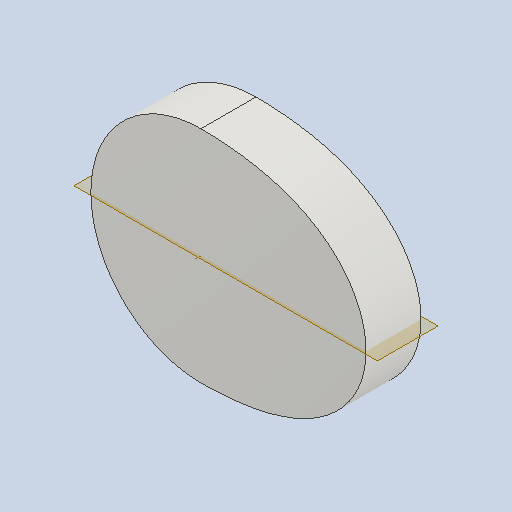
# Autodesk Inventor part: Disc Cam
Saved by Autodesk Inventor 2025.2 (Build 292293000, 293)
## iProperties
CustomPartVersion: 1
Created: 2025-05-16
Part Number: Disc Cam
Material: Stainless Steel, Austenitic
Document SubType Name: Modeling
Designer: laura
Manufacturer: Standard
Standards Organization: Custom
Density: 1 g/cm^3
Appearance: Steel
Author: laura
Autodesk Inventor part; units mm, degrees
ref_plane "YZ Plane" through (0, 0, 0) normal (1, 0, 0) x (0, 1, 0)
ref_plane "XY Plane" through (0, 0, 0) normal (0, 0, 1) x (1, 0, 0)
sketch "Main Sketch" plane through (0, 0, 0) normal (0, 0, 1) x (1, 0, 0)
  spline S0 degree 5 poles (0, 12) (0.4028, 12.0029) (1.1352, 11.9904) (2.4035, 11.9385) (3.7305, 11.8234) (5.6073, 11.5664) (7.2429, 11.2248) (8.9199, 10.7506) (10.4855, 10.155) (11.9526, 9.4335) (13.2947, 8.5866) (14.5002, 7.6184) (15.5512, 6.5376) (16.4335, 5.357) (17.1335, 4.0932) (17.641, 2.7651) (17.9484, 1.3935) (18.0513, 0) (17.9484, -1.3935) (17.641, -2.7651) (17.1335, -4.0932) (16.4335, -5.357) (15.5512, -6.5376) (14.5002, -7.6184) (13.2947, -8.5866) (11.9526, -9.4335) (10.4857, -10.1549) (8.9195, -10.7506) (7.2438, -11.2248) (5.5475, -11.5786) (3.7134, -11.8248) (2.115, -11.9626) (0.0437, -12.0261) (-1.0836, -11.9872) (-2.4837, -11.7795) (-3.6974, -11.4488) (-4.8987, -10.9923) (-6.0146, -10.421) (-7.0736, -9.7348) (-8.0513, -8.9422) (-8.9424, -8.0516) (-9.7348, -7.0728) (-10.4209, -6.0165) (-10.9926, -4.8942) (-11.444, -3.7184) (-11.77, -2.5018) (-11.967, -1.2578) (-12.0329, 0) (-11.967, 1.2578) (-11.77, 2.5018) (-11.444, 3.7184) (-10.9926, 4.8942) (-10.4209, 6.0165) (-9.7348, 7.0728) (-8.9424, 8.0516) (-8.0511, 8.9423) (-7.074, 9.7348) (-6.0137, 10.421) (-4.9008, 10.9922) (-3.7511, 11.4269) (-2.5835, 11.7561) (-1.505, 11.9244) (-0.839, 11.9821) (-0.3306, 11.9976) (0, 12) knots 0 0 0 0 0 0 0.0229 0.038048 0.056871 0.075478 0.093836 0.111931 0.129762 0.147341 0.164681 0.181803 0.198727 0.215484 0.232106 0.248635 0.265115 0.281595 0.298123 0.314745 0.331502 0.348427 0.365548 0.382888 0.400467 0.418299 0.436394 0.454752 0.473359 0.492181 0.510462 0.528146 0.545187 0.561547 0.577207 0.592866 0.608525 0.624184 0.639843 0.655502 0.671161 0.68682 0.702479 0.718138 0.733797 0.749456 0.765115 0.780774 0.796433 0.812092 0.827751 0.84341 0.859069 0.874728 0.890387 0.906046 0.921705 0.937364 0.953023 0.968682 0.981209 1 1 1 1 1 1
  point P0 (3.7362, 11.8007)
  point P1 (5.5442, 11.5465)
  point P2 (7.2858, 11.1825)
  point P3 (8.9458, 10.7026)
  point P4 (10.5106, 10.1017)
  point P5 (11.9666, 9.3769)
  point P6 (13.2995, 8.5285)
  point P7 (14.4938, 7.561)
  point P8 (15.5341, 6.4833)
  point P9 (16.4058, 5.3086)
  point P10 (17.0965, 4.0536)
  point P11 (17.5963, 2.7369)
  point P12 (17.8988, 1.3788)
  point P13 (18, 0)
  point P14 (17.8988, -1.3788)
  point P15 (17.5963, -2.7369)
  point P16 (17.0965, -4.0536)
  point P17 (16.4058, -5.3086)
  point P18 (15.5341, -6.4833)
  point P19 (14.4938, -7.561)
  point P20 (13.2995, -8.5285)
  point P21 (11.9666, -9.3769)
  point P22 (10.5106, -10.1017)
  point P23 (8.9458, -10.7026)
  point P24 (7.2858, -11.1825)
  point P25 (5.5442, -11.5465)
  point P26 (3.7362, -11.8007)
  point P27 (1.8807, -11.9505)
  point P28 (0, -12)
  point P29 (-1.2543, -11.9343)
  point P30 (-2.4949, -11.7378)
  point P31 (-3.7082, -11.4127)
  point P32 (-4.8808, -10.9625)
  point P33 (-6, -10.3923)
  point P34 (-7.0534, -9.7082)
  point P35 (-8.0296, -8.9177)
  point P36 (-8.9177, -8.0296)
  point P37 (-9.7082, -7.0534)
  point P38 (-10.3923, -6)
  point P39 (-10.9625, -4.8808)
  point P40 (-11.4127, -3.7082)
  point P41 (-11.7378, -2.4949)
  point P42 (-11.9343, -1.2543)
  point P43 (-12, 0)
  point P44 (-11.9343, 1.2543)
  point P45 (-11.7378, 2.4949)
  point P46 (-11.4127, 3.7082)
  point P47 (-10.9625, 4.8808)
  point P48 (-10.3923, 6)
  point P49 (-9.7082, 7.0534)
  point P50 (-8.9177, 8.0296)
  point P51 (-8.0296, 8.9177)
  point P52 (-7.0534, 9.7082)
  point P53 (-6, 10.3923)
  point P54 (-4.8808, 10.9625)
  point P55 (-3.7082, 11.4127)
  point P56 (-2.4949, 11.7378)
  point P57 (-1.2543, 11.9343)
  constraints: 60 other
extrude "Cam" add sketch "Main Sketch" along normal blind 6
body "Solid1"
